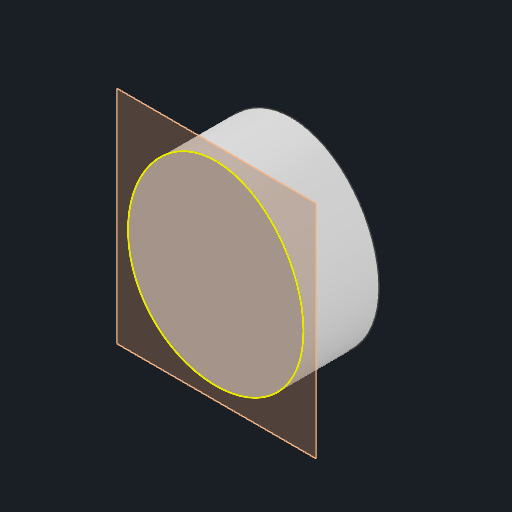
# Autodesk Inventor part: projected-closed
Saved by Autodesk Inventor 2026.1 (Build 301233000, 233)
## iProperties
Created: 2026-10-30
Part Number: projected-closed
Material: Generic
Document SubType Name: Modeling
Designer: anony
Density: 1 g/cm^3
Appearance: Default
Author: anony
Autodesk Inventor part; units mm, degrees
ref_plane "YZ Plane" through (0, 0, 0) normal (1, 0, 0) x (0, 1, 0)
ref_plane "XZ Plane" through (0, 0, 0) normal (0, 1, 0) x (-1, 0, 0)
sketch "Sketch1" plane through (0, 0, 0) normal (0, 0, 1) x (1, 0, 0)
  spline S0 degree 4 poles (0, 0) (0.7853, -1.3844) (2.8379, -3.8243) (7.1616, -6.1459) (13.7461, -5.9032) (19.248, -2.373) (22.0797, 3.6809) (21.5949, 10.7539) (18.1215, 16.9312) (12.6379, 20.4437) (6.5144, 20.1617) (1.2376, 16.1836) (-1.8605, 9.7637) (-1.874, 4.4821) (-0.7853, 1.3844) (0, 0) knots 0 0 0 0 0 0.083333 0.166667 0.25 0.333333 0.416667 0.5 0.583333 0.666667 0.75 0.833333 0.916667 1 1 1 1 1
  point P0 (20, 0)
  constraints: 3 other
extrude "Extrusion1" add sketch "Sketch1" along normal blind 10
ref_plane "Work Plane1" through (0, 0, 10) normal (0, 0, 1) x (1, 0, 0)
sketch "Sketch2" plane through (0, 0, 10) normal (0, 0, 1) x (1, 0, 0)
  constraints: 1 other
body "Solid1"
